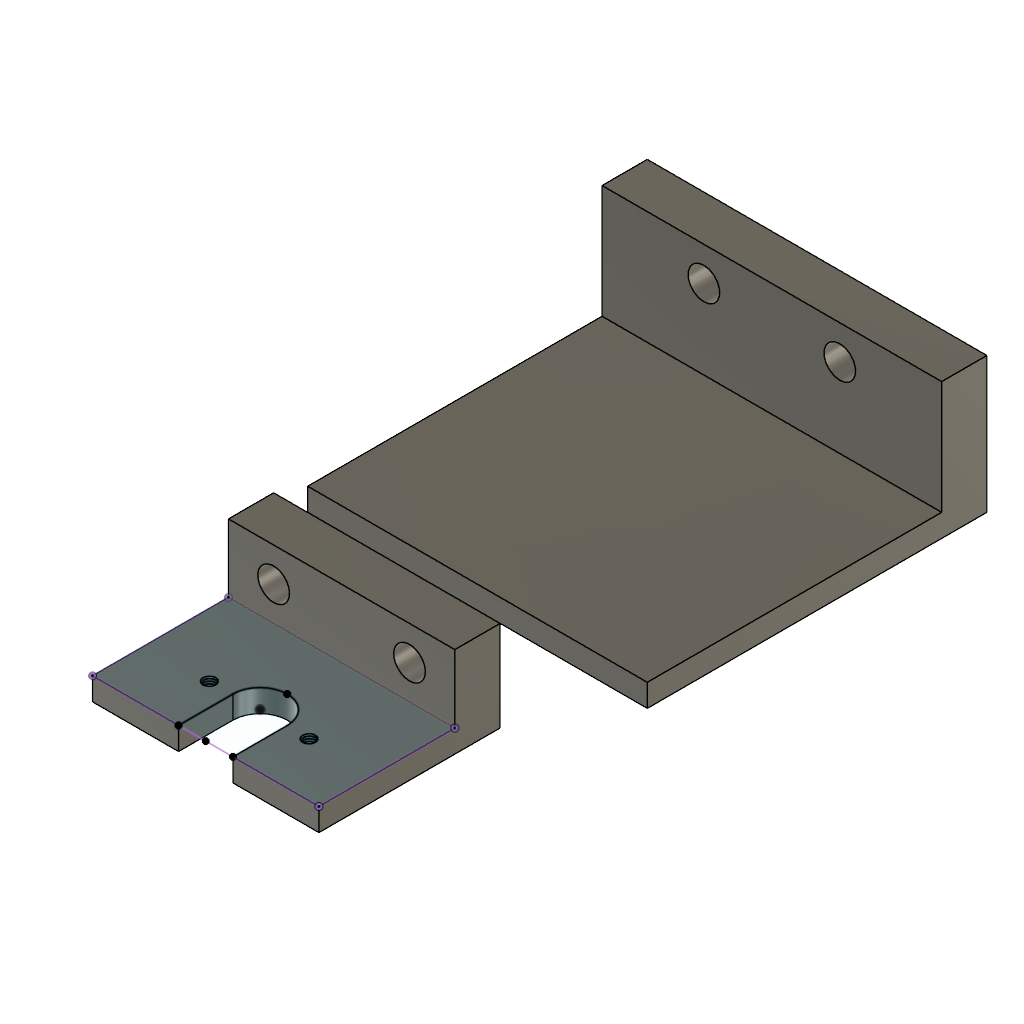
Rig (Autodesk Fusion 360 design; units mm, degrees)
Autodesk Fusion 360 part; units mm, degrees
note: some values were not read from the file. Set by a fixed rule: the direction of a hole.
sketch "Sketch1" plane through (0, 0, 0) normal (1, 0, 0) x (0, 1, 0)
  line L0 (0, 0) -> (0, 15)
  line L1 (0, 15) -> (10, 15)
  line L2 (10, 15) -> (10, -5)
  line L3 (10, -5) -> (-30, -5)
  line L4 (-30, -5) -> (-30, 0)
  line L5 (-30, 0) -> (0, 0)
  dimension "d21" = 40
  dimension "d22" = 20
  dimension "d23" = 10
  dimension "d24" = 5
  constraint coincident L0.start L5.end
  constraint vertical L0
  constraint perpendicular L0 L1
  constraint perpendicular L1 L2
  constraint perpendicular L2 L3
  constraint perpendicular L3 L4
  constraint perpendicular L0 L5
  measures "d21" distance of L2.end L3.end
  measures "d22" distance of L1.end L2.end
  measures "d23" distance of L0.end L1.end
  measures "d24" distance of L3.end L4.end
extrude "Extrude1" add sketch "Sketch1" along normal mid plane 50 makes body 1
sketch "Sketch2" plane through (0, 0, 0) normal (0, 1, 0) x (-1, 0, 0)
  line L0 (25, 0) -> (25, 25)
  line L1 (25, 25) -> (-25, 25)
  line L2 (-25, 25) -> (-25, 0)
  line L3 (-25, 0) -> (25, 0)
  line L4 (25, 0) -> (-25, 0)
  line L5 (-25, 0) -> (-25, 15)
  line L6 (-25, 15) -> (25, 15)
  line L7 (25, 15) -> (25, 0)
  line L8 (0, 1.75) -> (0, 22.5)
  point P0 (15, 7.5)
  point P1 (-15, 7.5)
  dimension "d34" = 30
  dimension "d60" = 7.5
  constraint symmetric P0 P1 L8
  measures "d34" distance of P0 P1
  measures "d60" vertical distance of P1 L5.end
sketch "Sketch3" plane through (0, 0, 0) normal (0, 0, 1) x (-1, 0, 0)
  line L0 (25, 0) -> (-25, 0)
  line L1 (-6, 30) -> (-6, 18)
  arc A0 (-6, 18) -> (6, 18) centre (0, 18) ccw
  line L2 (6, 18) -> (6, 30)
  line L3 (25, 30) -> (-25, 30)
  line L4 (-25, 30) -> (-25, 0)
  line L5 (-25, 0) -> (25, 0)
  line L6 (25, 0) -> (25, 30)
  point P0 (0, 30)
  point P1 (0, 12)
  dimension "d26" = 6
  dimension "d40" = 12
  constraint coincident L1.start L3
  constraint coincident L2.end L3
  constraint tangent A0 L2
  constraint tangent L1 A0
  constraint vertical L2
  constraint vertical L1
  constraint midpoint L3 P0
  constraint vertical A0.centre P0
  constraint midpoint A0 P1
  measures "d26" radius of A0
  measures "d40" distance of L0 P1
extrude "Extrude2" cut sketch "Sketch3" against normal blind 10 contours L1 A0 L2 L3 bodies 1
sketch "Sketch4" plane through (0, 0, -5) normal (0, 0, 1) x (-1, 0, 0)
  line L0 (0, -1.75) -> (0, -22.5)
  line L1 (-6, 30) -> (-6, 18)
  arc A0 (-6, 18) -> (6, 18) centre (0, 18) ccw
  line L2 (6, 18) -> (6, 30)
  line L3 (6, 30) -> (25, 30)
  line L4 (25, 30) -> (25, -10)
  line L5 (25, -10) -> (-25, -10)
  line L6 (-25, -10) -> (-25, 30)
  line L7 (-25, 30) -> (-6, 30)
  point P0 (11, 18)
  point P1 (-11, 18)
  point P2 (0, 11)
  point P3 (0, 18)
  dimension "d35" = 22
  constraint symmetric P0 P1 L0
  constraint horizontal P0 P3
  measures "d35" distance of P0 P1
hole "Hole2" at (11, -18, -5) at (-11, -18, -5) direction (0, 0, 1) diameter 2.529 end through all counterbore diameter 5.5 counterbore depth 2.5 bodies 1 1
sketch "Sketch5" plane through (0, 0, 0) normal (1, 0, 0) x (0, 1, 0)
  line L0 (30, -5) -> (105, -5)
  line L1 (105, -5) -> (105, 25)
  line L2 (105, 25) -> (95, 25)
  line L3 (95, 25) -> (95, 0)
  line L4 (95, 0) -> (30, 0)
  line L5 (30, 0) -> (30, -5)
  line L6 (10, 15) -> (0, 15)
  line L7 (10, -5) -> (10, 15)
  line L8 (-30, 0) -> (-30, -5)
  dimension "d47" = 75
  dimension "d58" = 30
  dimension "d59" = 30
  constraint horizontal L0
  constraint perpendicular L0 L1
  constraint perpendicular L1 L2
  constraint perpendicular L2 L3
  constraint perpendicular L3 L4
  constraint perpendicular L0 L5
  constraint equal L2 L6
  constraint equal L5 L8
  constraint horizontal origin L3.end
  measures "d47" distance of L0.start L0.end
  measures "d58" distance of L0.end L1.end
  measures "d59" horizontal distance of origin L4.end
extrude "Extrude5" add sketch "Sketch5" along normal mid plane 75 separate body makes body 2
hole "Hole1" at (15, 0, 7.5) at (-15, 0, 7.5) direction (0, 1, 0) diameter 4.234 depth 20 tip angle 118 counterbore diameter 7 counterbore depth 5 bodies 1
sketch "Sketch7" plane through (0, 95, 0) normal (0, -1, 0) x (1, 0, 0)
  line L0 (-37.5, 0) -> (37.5, 0)
  line L1 (37.5, 0) -> (37.5, 25)
  line L2 (37.5, 25) -> (-37.5, 25)
  line L3 (-37.5, 25) -> (-37.5, 0)
  point P0 (-15, 17.5)
  point P1 (15, 17.5)
  point P2 (-15, 4)
  point P3 (15, 4)
  dimension "d61" = 7.5
  constraint vertical P0 P2
  constraint vertical P1 P3
  constraint horizontal P0 P1
  measures "d61" vertical distance of L2.end P0
hole "Hole3" at (15, 95, 17.5) at (-15, 95, 17.5) direction (0, 1, 0) diameter 4.234 depth 20 tip angle 118 counterbore diameter 7 counterbore depth 5 bodies 2
